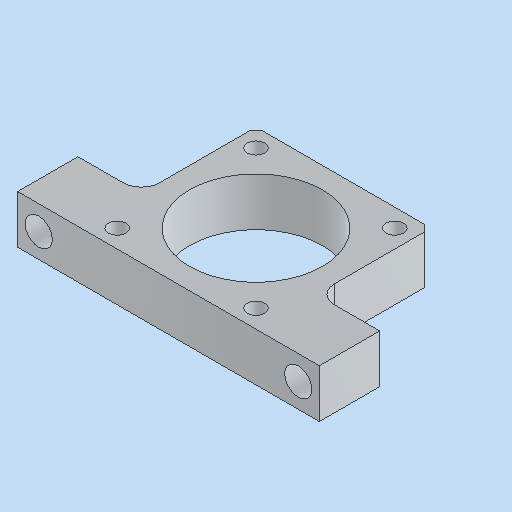
# Autodesk Inventor part: MM0948AN130_G13_100
Saved by Autodesk Inventor 2023.3 (Build 273359000, 359)
## iProperties
Created: 2024-11-11
Part Number: MM0948AN130_G13_100
Material: 3.3547 AlMg4,5Mn0,7 - AW 5083
Description: =<RBPARTNOTITLE2>
Document SubType Name: Modeling
Designer: RIC7AN
Mass: 4.86039 g
Surface Area: 35.9223 cm^2
Volume: 4.86039 cm^3
Density: 1 g/cm^3
Appearance: Aluminium AnP
RBPARTMADEOF: 8 x 29 x 50 (FM)
RBDRAWINGMISSINGSPEC: --
AnP_Kategorie: 1
RBPARTNOTITLE2: Anfertigungsteil
RBSURFACE: anodised colourless
RBPARTNOTITLE1: manufactured part
RBSURFACE2: eloxiert farblos
AnP_Material: =<Material>
RBMATERIAL: =<Material>
RBMATNO: =<Part Number>
RBPARTNO: SIEHE MNR
MaxAbmaße: 8 x 29 x 50 (FM)
Author: RIC7AN
Keywords: =<RBPARTMADEOF>
Comments: =<RBSURFACE2>
Revision Number: 01
Autodesk Inventor part; units mm, degrees
ref_plane "YZ Plane" through (0, 0, 0) normal (1, 0, 0) x (0, 1, 0)
ref_plane "XZ Plane" through (0, 0, 0) normal (0, 1, 0) x (-1, 0, 0)
ref_plane "XY Plane" through (0, 0, 0) normal (0, 0, 1) x (1, 0, 0)
sketch "Skizze1" plane through (0, 0, 0) normal (0, 0, 1) x (1, 0, 0)
  line L0 (-14.5, 14.5) -> (14.5, 14.5)
  line L1 (14.5, 14.5) -> (14.5, -14.5)
  line L2 (14.5, -14.5) -> (-14.5, -14.5)
  line L3 (-14.5, -14.5) -> (-14.5, 14.5)
  line L4 (0, 20.3) -> (0, -20.3) projected
  line L5 (-20.3, 0) -> (20.3, 0) projected
  point P0 (0, 0)
  dimension "d0" = 29
  dimension "d1" = 29
  constraints: 8 end point, 2 parallel, 1 horizontal, 1 perpendicular, 2 other
  measures "d0" distance of L0.start L0.end
  measures "d1" distance of L2.end L0.start
extrude "Extrusion1" add sketch "Skizze1" along normal mid plane 8
sketch "Skizze2" plane through (0, 0, -4) normal (0, 0, -1) x (-1, 0, 0)
  point P0 (0, 0)
  point P1 (0, 0)
  constraints: 1 coincident
hole "Bohrung1" at (0, 0, -4) direction (0, 0, 1) diameter 22 end through all
sketch "Skizze3" plane through (0, 0, -4) normal (0, 0, -1) x (-1, 0, 0)
  line L0 (0, -20.3) -> (0, 20.3) projected
  line L1 (-20.3, 0) -> (20.3, 0) projected
  point P0 (0, 0)
  point P1 (-11.5, 11.5)
  point P2 (11.5, 11.5)
  point P3 (11.5, -11.5)
  point P4 (-11.5, -11.5)
  dimension "d11" = 23
  dimension "d12" = 23
  constraints: 4 symmetric about line
  measures "d11" distance of point (11.5, 11.5) point (-11.5, 11.5)
  measures "d12" distance of point (-11.5, -11.5) point (-11.5, 11.5)
hole "Bohrung2" at (11.5, 11.5, -4) at (-11.5, 11.5, -4) at (-11.5, -11.5, -4) at (11.5, -11.5, -4) direction (0, 0, 1) diameter 2.9 end through all clearance for "Inbusschraube ISO 4762  versenkt" size "M2.5" standard "ISO"
sketch "Skizze4" plane through (0, 0, 4) normal (0, 0, 1) x (1, 0, 0)
  line L0 (14.5, -14.5) -> (14.5, 14.5) projected
  line L1 (-14.5, 14.5) -> (-14.5, -14.5) projected
  line L2 (-14.5, -14.5) -> (14.5, -14.5) projected
  line L3 (14.5, -14.5) -> (25, -14.5)
  line L4 (25, -14.5) -> (25, -4.5)
  line L5 (25, -4.5) -> (14.5, -4.5)
  line L6 (14.5, -4.5) -> (14.5, -14.5)
  line L7 (-14.5, -14.5) -> (-25, -14.5)
  line L8 (-25, -14.5) -> (-25, -4.5)
  line L9 (-25, -4.5) -> (-14.5, -4.5)
  line L10 (-14.5, -4.5) -> (-14.5, -14.5)
  line L11 (0, 20.3) -> (0, -20.3) projected
  point P0 (0, 0)
  point P1 (14.5, -4.5)
  point P2 (-14.5, -4.5)
  dimension "d20" = 10
  dimension "d21" = 10.5
  constraints: 16 end point, 4 parallel, 2 horizontal, 2 perpendicular, 1 collinear, 1 other
  measures "d20" distance of L7.end L8.end
  measures "d21" distance of L1.end L7.end
extrude "Extrusion2" add sketch "Skizze4" against normal up to surface (8 mm away)
fillet "Rundung1" radius 3 2 edges at (-14.5, -4.5, 0) (14.5, -4.5, 0)
sketch "Skizze5" plane through (-25, -4.5, 4) normal (0, 1, 0) x (1, 0, 0)
  line L0 (60, 4) -> (-10, 4) projected
  line L1 (25, 9.6) -> (25, -1.6) projected
  point P0 (25, 4)
  point P1 (3.5, 4)
  point P2 (46.5, 4)
  dimension "d25" = 43
  constraints: 2 point on line, 1 symmetric about line
  measures "d25" distance of point (46.5, 4) point (3.5, 4)
hole "Bohrung3" at (-21.5, -4.5, 0) at (21.5, -4.5, 0) direction (0, -1, 0) diameter 4.5 end through all clearance for "Inbusschraube ISO 4762  versenkt" size "M4" standard "ISO"
chamfer "Fase1" distance 1 angle 45 2 edges at (-14.5, 14.5, 0) (14.5, 14.5, 0)
equation "\"d1\" = d0"
